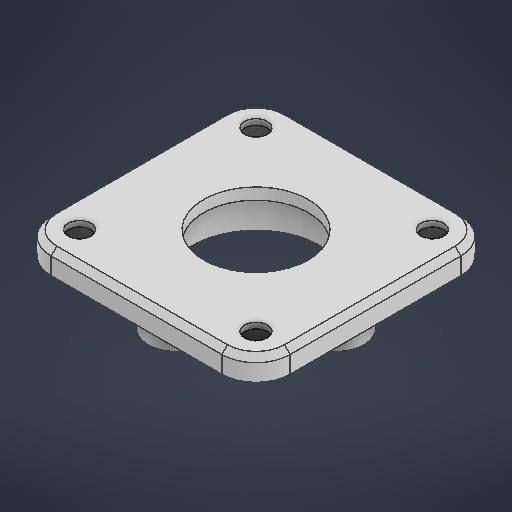
# Autodesk Inventor part: liner608_holder
Saved by Autodesk Inventor 2026.2 (Build 302298010, 298A)
## iProperties
Created: 2026-04-23
Part Number: liner608_holder
Material: 일반
Document SubType Name: Modeling
Designer: work
Density: 1 g/cm^3
Appearance: 기본값
Author: work
Autodesk Inventor part; units mm, degrees
ref_plane "YZ Plane" through (0, 0, 0) normal (1, 0, 0) x (0, 1, 0)
ref_plane "XZ Plane" through (0, 0, 0) normal (0, 1, 0) x (-1, 0, 0)
ref_plane "XY Plane" through (0, 0, 0) normal (0, 0, 1) x (1, 0, 0)
sketch "스케치1" plane through (0, 0, 0) normal (0, 1, 0) x (-1, 0, 0)
  line L0 (-15.5, 15.5) -> (15.5, 15.5) construction
  line L1 (15.5, 15.5) -> (15.5, -15.5) construction
  line L2 (15.5, -15.5) -> (-15.5, -15.5) construction
  line L3 (-15.5, -15.5) -> (-15.5, 15.5) construction
  line L4 (-15.5, 15.5) -> (15.5, -15.5) construction
  line L5 (15.5, 15.5) -> (-15.5, -15.5) construction
  circle A0 centre (0, 0) radius 11.2
  circle A1 centre (15.5, 15.5) radius 2
  circle A2 centre (15.5, -15.5) radius 2
  circle A3 centre (-15.5, -15.5) radius 2
  circle A4 centre (-15.5, 15.5) radius 2
  line L6 (-21, 21) -> (21, 21)
  line L7 (21, 21) -> (21, -21)
  line L8 (21, -21) -> (-21, -21)
  line L9 (-21, -21) -> (-21, 21)
  line L10 (-21, 21) -> (21, -21) construction
  line L11 (21, 21) -> (-21, -21) construction
  dimension "d0" = 31
  dimension "d1" = 31
  dimension "d2" = 22.4
  dimension "d3" = 4
  dimension "d4" = 4
  dimension "d5" = 4
  dimension "d6" = 4
  dimension "d7" = 42
  constraints: 24 end point, 5 centre point, 4 coincident, 4 midpoint, 4 parallel, 2 horizontal, 2 perpendicular, 2 point on line
  measures "d0" distance of L1.end L2.end
  measures "d1" distance of L0.end L1.end
  measures "d2" diameter of A0
  measures "d3" diameter of A1
  measures "d4" diameter of A2
  measures "d5" diameter of A3
  measures "d6" diameter of A4
  measures "d7" distance of L6.end L7.end
extrude "돌출1" add sketch "스케치1" along normal blind 4
sketch "스케치2" plane through (0, 4, 0) normal (0, 1, 0) x (1, 0, 0)
  point P0 (0, 0)
sketch "스케치3" plane through (0, 4, 0) normal (0, 1, 0) x (1, 0, 0)
  circle A0 centre (0, 0) radius 9.2
  circle A1 centre (0, 0) radius 11.2 projected
  dimension "d10" = 2
  constraints: 1 centre point, 1 coincident
  measures "d10" radial gap between concentric circles of A1 A0
extrude "돌출2" add sketch "스케치3" against normal blind 2
sketch "스케치4" plane through (0, 0, 0) normal (0, -1, 0) x (1, 0, 0)
  line L0 (21, -21) -> (-21, -21) projected
  line L1 (21, 21) -> (21, -21) projected
  line L2 (-21, 21) -> (21, 21) projected
  line L3 (-21, -21) -> (-21, 21) projected
  circle A0 centre (15.5, 15.5) radius 2 projected
  circle A1 centre (15.5, -15.5) radius 2 projected
  circle A2 centre (-15.5, -15.5) radius 2 projected
  circle A3 centre (-15.5, 15.5) radius 2 projected
  circle A4 centre (0, 0) radius 11.2 projected
  circle A5 centre (0, 0) radius 15.2
  circle A6 centre (14, 0) radius 2
  line L4 (14, 0) -> (0, 0) construction
  line L5 (0, 0) -> (0, 15.2) construction
  circle A7 centre (14, 0) radius 5
  circle A8 centre (0, 14) radius 2
  circle A9 centre (0, 14) radius 5
  line L6 (0, 14) -> (0, 0) construction
  circle A10 centre (-14, 0) radius 2
  circle A11 centre (-14, 0) radius 5
  line L7 (-14, 0) -> (0, 0) construction
  circle A12 centre (0, -14) radius 2
  circle A13 centre (0, -14) radius 5
  line L8 (0, -14) -> (0, 0) construction
  point P0 (14.3586, 4.9871)
  point P1 (4.9871, 14.3586)
  point P2 (-4.9871, 14.3586)
  point P3 (-14.3586, 4.9871)
  point P4 (-14.3586, -4.9871)
  point P5 (14.3586, -4.9871)
  point P6 (-4.9871, -14.3586)
  point P7 (4.9871, -14.3586)
  dimension "d13" = 4
  dimension "d16" = 4
  dimension "d17" = 14
  dimension "d18" = 3
  dimension "d21" = 360
  constraints: 10 end point, 8 centre point, 5 coincident, 1 horizontal, 1 perpendicular, 28 other
  measures "d16" diameter of A6
  measures "d17" distance of A4.centre L4.start
  measures "d18" radial gap between concentric circles of A7 A6
extrude "돌출3" add sketch "스케치4" along normal blind 4 contours A4 A7 A5 A6 | A4 A9 A5 A7 | A7 A5 A13 A4 | A4 A9 A5 A8 | A7 A5 A6 | A13 A5 A12 A4 | A4 A11 A5 A9 | A5 A8 A9 | A13 A5 A11 A4 | A13 A5 A12 | A4 A11 A5 A10 | A5 A10 A11
fillet "모깎기1" radius 2 8 edges at (-10.748, 0, 10.748) (0, 0, 19) (10.748, 0, 10.748) (19, 0, 0) (-10.748, 0, -10.748) (10.748, 0, -10.748) (-19, 0, 0) (0, 0, -19)
fillet "모깎기2" radius 6 4 edges at (-21, 2, -21) (21, 2, -21) (21, 2, 21) (-21, 2, 21)
sketch "스케치5" plane through (0, 0, 0) normal (0, -1, 0) x (1, 0, 0)
  circle A0 centre (15.5, 15.5) radius 2 projected
  circle A1 centre (15.5, -15.5) radius 2 projected
  circle A2 centre (-15.5, -15.5) radius 2 projected
  circle A3 centre (-15.5, 15.5) radius 2 projected
  point P0 (0, 0)
  constraints: 4 coincident
hole "구멍1" at (15.5, 0, 15.5) at (15.5, 0, -15.5) at (-15.5, 0, -15.5) at (-15.5, 0, 15.5) direction (0, 1, 0) diameter 3.8 end through all counterbore diameter 6.2 counterbore depth 3
chamfer "모따기1" distance 1 angle 45 8 edges at (19.2426, 4, 19.2426) (0, 4, 21) (-19.2426, 4, 19.2426) (-21, 4, 0) (-19.2426, 4, -19.2426) (0, 4, -21) (19.2426, 4, -19.2426) (21, 4, 0)
